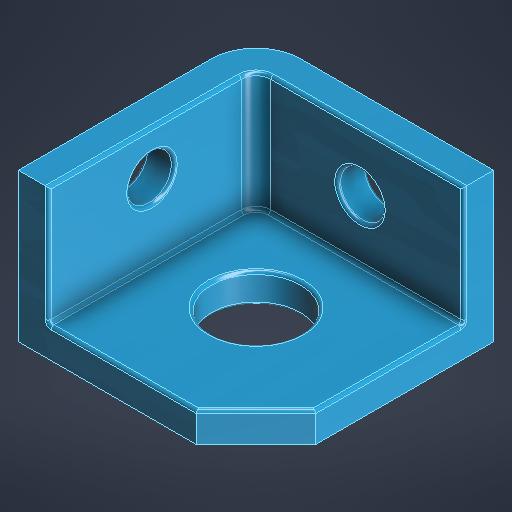
# Autodesk Inventor part: Youtube_example
Saved by Autodesk Inventor 2026.4 (Build 304435000, 435)
## iProperties
Created: 2026-11-06
Part Number: Youtube_example
Material: Stainless Steel
Document SubType Name: Modeling
Designer: s79iycbl
Density: 8 g/cm^3
Appearance: Sky Blue Dark
Author: s79iycbl
Autodesk Inventor part; units mm, degrees
ref_plane "YZ Plane" through (0, 0, 0) normal (1, 0, 0) x (0, 1, 0)
ref_plane "XZ Plane" through (0, 0, 0) normal (0, 1, 0) x (-1, 0, 0)
ref_plane "XY Plane" through (0, 0, 0) normal (0, 0, 1) x (1, 0, 0)
sketch "Sketch2" plane through (0, 0, 0) normal (0, 1, 0) x (-1, 0, 0)
  line L0 (0, 0) -> (80, 0)
  line L1 (80, 0) -> (80, -80)
  line L2 (80, -80) -> (0, -80)
  line L3 (0, -80) -> (0, 0)
  circle A0 centre (40, -40) radius 15
  line L4 (21.634, 0) -> (20.7966, 0)
  line L5 (20, 0) -> (0, -20)
  point P0 (80, -40)
  dimension "d2" = 80
  dimension "d3" = 80
  dimension "d4" = 30
  dimension "d5" = 40
  dimension "d6" = 40
  dimension "d7" = 20
  dimension "d8" = 20
  constraints: 12 end point, 4 point on line, 2 parallel, 1 centre point, 1 horizontal, 1 midpoint, 1 perpendicular
  measures "d2" distance of L0.end L1.end
  measures "d3" distance of L0.start L0.end
  measures "d4" diameter of A0
  measures "d5" distance of point (80, -40) A0.centre
  measures "d6" distance from line of L2 A0.centre
  measures "d7" distance of L0.start L5.start
  measures "d8" distance of L5.end L0.start
extrude "Extrusion2" add sketch "Sketch2" along normal blind 10 contours L0 L1 L2 L3 L5
sketch "Sketch3" plane through (0, 10, 0) normal (0, 1, 0) x (1, 0, 0)
  line L0 (0, 80) -> (-80, 80) projected
  line L1 (-80, 0) -> (-20, 0) projected
  line L2 (-80, 80) -> (-70, 80)
  line L3 (-70, 80) -> (-70, 0)
  line L4 (-70, 0) -> (-80, 0)
  line L5 (-80, 0) -> (-80, 80)
  line L6 (0, 20) -> (0, 80) projected
  line L7 (-80, 80) -> (0, 80)
  line L8 (0, 80) -> (0, 70)
  line L9 (0, 70) -> (-80, 70)
  line L10 (-80, 70) -> (-80, 80)
  point P0 (0, 0)
  point P1 (-70, 70)
  dimension "d11" = 10
  dimension "d12" = 10
  constraints: 16 end point, 4 parallel, 2 horizontal, 2 perpendicular, 2 point on line
  measures "d11" distance between parallel lines of L3 L5
  measures "d12" distance between parallel lines of L9 L0
extrude "Extrusion3" add sketch "Sketch3" along normal blind 40
fillet "Fillet1" radius 5 1 edges at (-70, 30, -70)
fillet "Fillet2" radius 15 1 edges at (-80, 25, -80)
sketch "Sketch4" plane through (0, 10, -70) normal (0, 0, 1) x (1, 0, 0)
  circle A0 centre (-35, 20) radius 7.5
  line L0 (-65, 40) -> (0, 40) projected
  line L1 (0, 0) -> (0, 40) projected
  point P0 (0, -10)
  dimension "d17" = 15
  dimension "d18" = 20
  dimension "d19" = 35
  constraints: 1 centre point
  measures "d17" diameter of A0
  measures "d18" distance from line of L0 A0.centre
  measures "d19" distance from line of L1 A0.centre
extrude "Extrusion4" cut sketch "Sketch4" against normal blind 40
sketch "Sketch5" plane through (-70, 10, 0) normal (1, 0, 0) x (0, 0, -1)
  circle A0 centre (35, 25) radius 7.5
  line L0 (0, 40) -> (65, 40) projected
  line L1 (0, 0) -> (0, 40) projected
  point P0 (0, -10)
  dimension "d22" = 15
  dimension "d23" = 15
  dimension "d24" = 35
  constraints: 1 centre point
  measures "d22" diameter of A0
  measures "d23" distance from line of L0 A0.centre
  measures "d24" distance from line of L1 A0.centre
extrude "Extrusion5" cut sketch "Sketch5" against normal blind 40
fillet "Fillet3" radius 1 16 edges at (-32.5, 50, -70) (-70, 50, -32.5) (-70, 35, -27.5) (-42.5, 30, -70) (-70, 30, 0) (-68.5355, 10, -68.5355) (-32.5, 10, -70) (-70, 10, -32.5) (-45, 10, 0) (-10, 10, -10) (0, 10, -45) (0, 30, -70) (-25, 10, -40) (-25, 0, -40) (-42.5, 30, -80) (-80, 35, -27.5)
body "Solid2"
